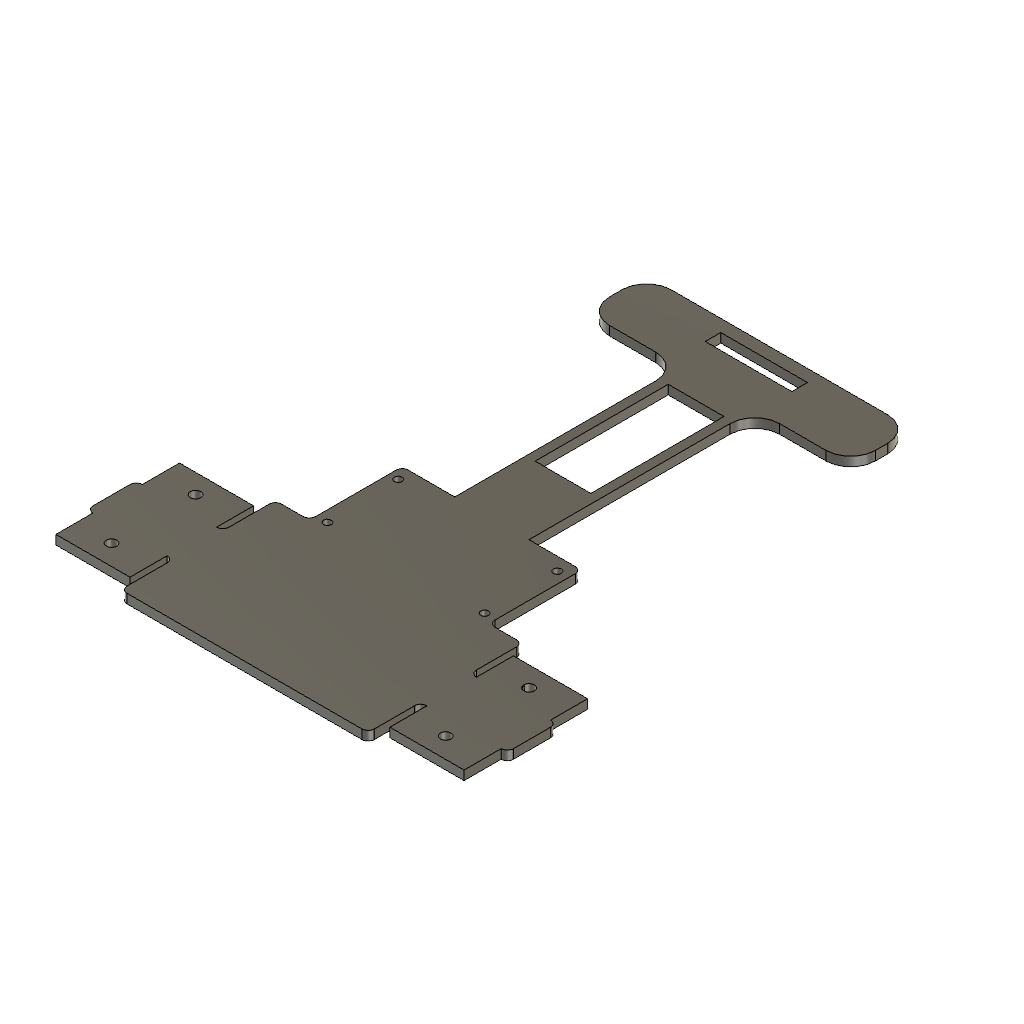
LFR Chassis (Autodesk Fusion 360 design; units mm, degrees)
part number: 2026-11-09-15-47-56-464
Autodesk Fusion 360 part; units mm, degrees
sketch "Sketch1" plane through (0, 0, 0) normal (0, 0, 1) x (1, 0, 0)
  line L0 (-30, 80) -> (10, 80)
  line L1 (10, 80) -> (10, -110)
  line L2 (10, -110) -> (-30, -110)
  line L3 (-30, -110) -> (-30, 80)
  dimension "d1" = 40
  dimension "d2" = 190
  constraint horizontal L0
  constraint vertical L1
  constraint horizontal L2
  constraint vertical L3
  measures "d1" distance of L0.start L0.end
  measures "d2" distance of L0.end L1.end
extrude "Extrude1" add sketch "Sketch1" along normal blind 3
sketch "Sketch2" plane through (10, 0, 0) normal (1, 0, 0) x (0, 1, 0)
  line L0 (-110, 0) -> (80, 0)
  line L1 (80, 0) -> (80, 3)
  line L2 (80, 3) -> (-110, 3)
  line L3 (-110, 3) -> (-110, 0)
  line L4 (80, 3) -> (50, 3)
  line L5 (50, 3) -> (50, 0)
  line L6 (50, 0) -> (80, 0)
  line L7 (80, 0) -> (80, 3)
  line L8 (80, 3) -> (50, 3)
  line L9 (50, 3) -> (50, 0)
  line L10 (50, 0) -> (80, 0)
  line L11 (80, 0) -> (80, 3)
  dimension "d5" = 30
  constraint horizontal L4
  constraint vertical L5
  constraint horizontal L6
  constraint vertical L7
  constraint coincident L1.end L2.start
  constraint horizontal L8
  constraint vertical L9
  constraint horizontal L10
  constraint vertical L11
  measures "d5" distance of L1.end L4.end
extrude "Extrude2" add sketch "Sketch2" along normal blind 45 contours L0 L1 L2 L4 L5 L6 L7 L8 L9 L10 L11
sketch "Sketch3" plane through (-30, 0, 0) normal (-1, 0, 0) x (0, -1, 0)
  line L0 (-80, 0) -> (110, 0)
  line L1 (110, 0) -> (110, 3)
  line L2 (110, 3) -> (-80, 3)
  line L3 (-80, 3) -> (-80, 0)
  line L4 (-80, 3) -> (-50, 3)
  line L5 (-50, 3) -> (-50, 0)
  line L6 (-50, 0) -> (-80, 0)
  line L7 (-80, 0) -> (-80, 3)
  constraint horizontal L4
  constraint vertical L5
  constraint horizontal L6
  constraint vertical L7
  constraint coincident L0 L5.end
  constraint coincident L2.end L3.start
extrude "Extrude3" add sketch "Sketch3" along normal blind 45 contours L0 L2 L3 L4 L5 L6 L7
sketch "Sketch4" plane through (10, 0, 0) normal (1, 0, 0) x (0, 1, 0)
  line L0 (50, 0) -> (50, 3)
  line L1 (50, 3) -> (-110, 3)
  line L2 (-110, 3) -> (-110, 0)
  line L3 (-110, 0) -> (50, 0)
  line L4 (-110, 3) -> (-50, 3)
  line L5 (-50, 3) -> (-50, 0)
  line L6 (-50, 0) -> (-110, 0)
  line L7 (-110, 0) -> (-110, 3)
  dimension "d10" = 60
  constraint horizontal L4
  constraint vertical L5
  constraint horizontal L6
  constraint vertical L7
  constraint coincident L1.end L2.start
  measures "d10" distance of L1.end L4.end
extrude "Extrude4" add sketch "Sketch4" along normal blind 40 contours L1 L2 L3 L4 L5 L6 L7
sketch "Sketch5" plane through (-30, 0, 0) normal (-1, 0, 0) x (0, -1, 0)
  line L0 (-50, 3) -> (-50, 0)
  line L1 (-50, 0) -> (110, 0)
  line L2 (110, 0) -> (110, 3)
  line L3 (110, 3) -> (-50, 3)
  line L4 (110, 3) -> (50, 3)
  line L5 (50, 3) -> (50, 0)
  line L6 (50, 0) -> (110, 0)
  line L7 (110, 0) -> (110, 3)
  dimension "d13" = 60
  constraint horizontal L4
  constraint vertical L5
  constraint horizontal L6
  constraint vertical L7
  constraint coincident L2.end L3.start
  measures "d13" distance of L2.end L4.end
extrude "Extrude5" add sketch "Sketch5" along normal blind 40 contours L1 L2 L3 L4 L5 L6 L7
extrude "Extrude6" cut 1 faces at (10, -110, 1) along direction (0, 1, 0) blind 10
extrude "Extrude7" cut 1 faces at (50, -83.3333, 2) along direction (-1, 0, 0) blind 20
extrude "Extrude8" cut 1 faces at (-70, -66.6667, 2) along direction (1, 0, 0) blind 20
sketch "Sketch6" plane through (-50, 0, 0) normal (-1, 0, 0) x (0, -1, 0)
  line L0 (100, 0) -> (100, 3)
  line L1 (100, 3) -> (50, 3)
  line L2 (50, 3) -> (50, 0)
  line L3 (50, 0) -> (100, 0)
  line L4 (60, 3) -> (90, 3)
  line L5 (90, 3) -> (90, 0)
  line L6 (90, 0) -> (60, 0)
  line L7 (60, 0) -> (60, 3)
  constraint horizontal L4
  constraint vertical L5
  constraint horizontal L6
  constraint vertical L7
  constraint coincident L3 L5.end
  constraint coincident L1 L4.start
extrude "Extrude9" add sketch "Sketch6" along normal blind 40 contours L1 L3 L4 L5 L6 L7
sketch "Sketch7" plane through (-90, 0, 0) normal (-1, 0, 0) x (0, -1, 0)
  line L0 (60, 0) -> (90, 0)
  line L1 (90, 0) -> (90, 3)
  line L2 (90, 3) -> (60, 3)
  line L3 (60, 3) -> (60, 0)
  line L4 (60, 3) -> (90, 3)
  line L5 (90, 3) -> (90, 0)
  line L6 (90, 0) -> (60, 0)
  line L7 (60, 0) -> (60, 3)
  constraint horizontal L4
  constraint vertical L5
  constraint horizontal L6
  constraint vertical L7
  constraint coincident L0.end L1.start
  constraint coincident L2.end L3.start
extrude "Extrude10" cut sketch "Sketch7" against normal blind 12
sketch "Sketch8" plane through (30, 0, 0) normal (1, 0, 0) x (0, 1, 0)
  line L0 (-100, 3) -> (-100, 0)
  line L1 (-100, 0) -> (-50, 0)
  line L2 (-50, 0) -> (-50, 3)
  line L3 (-50, 3) -> (-100, 3)
  line L4 (-90, 3) -> (-60, 3)
  line L5 (-60, 3) -> (-60, 0)
  line L6 (-60, 0) -> (-90, 0)
  line L7 (-90, 0) -> (-90, 3)
  constraint horizontal L4
  constraint vertical L5
  constraint horizontal L6
  constraint vertical L7
  constraint coincident L1 L5.end
  constraint coincident L3 L4.start
extrude "Extrude11" add sketch "Sketch8" along normal blind 28 contours L1 L3 L4 L5 L6 L7
extrude "Extrude12" cut 1 faces at (39.3333, -60, 2) along direction (0, -1, 0) blind 7
extrude "Extrude13" cut 1 faces at (39.3333, -90, 1) along direction (0, 1, 0) blind 7
extrude "Extrude14" cut 1 faces at (-68.6667, -90, 2) along direction (0, 1, 0) blind 7
extrude "Extrude15" cut 1 faces at (-68.6667, -60, 1) along direction (0, -1, 0) blind 7
extrude "Extrude16" add 1 faces at (-36.6667, -50, 2) along direction (0, 1, 0) blind 30
extrude "Extrude17" add 1 faces at (16.6667, -50, 2) along direction (0, 1, 0) blind 30
sketch "Sketch9" plane through (-50, 0, 0) normal (-1, 0, 0) x (0, -1, 0)
  line L0 (67, 3) -> (20, 3)
  line L1 (20, 3) -> (20, 0)
  line L2 (20, 0) -> (67, 0)
  line L3 (67, 0) -> (67, 3)
  line L4 (50, 3) -> (20, 3)
  line L5 (20, 3) -> (20, 0)
  line L6 (20, 0) -> (50, 0)
  line L7 (50, 0) -> (50, 3)
  constraint horizontal L4
  constraint vertical L5
  constraint horizontal L6
  constraint vertical L7
  constraint coincident L1.end L2.start
  constraint coincident L0 L4.start
extrude "Extrude18" cut sketch "Sketch9" against normal blind 11 contours L0 L1 L2 L4 L5 L6 L7
sketch "Sketch10" plane through (30, 0, 0) normal (1, 0, 0) x (0, 1, 0)
  line L0 (-67, 0) -> (-20, 0)
  line L1 (-20, 0) -> (-20, 3)
  line L2 (-20, 3) -> (-67, 3)
  line L3 (-67, 3) -> (-67, 0)
  line L4 (-50, 3) -> (-20, 3)
  line L5 (-20, 3) -> (-20, 0)
  line L6 (-20, 0) -> (-50, 0)
  line L7 (-50, 0) -> (-50, 3)
  constraint horizontal L4
  constraint vertical L5
  constraint horizontal L6
  constraint vertical L7
  constraint coincident L0.end L1.start
  constraint coincident L2 L4.start
extrude "Extrude19" cut sketch "Sketch10" against normal blind 11 contours L0 L1 L2 L4 L5 L6 L7
sketch "Sketch11" plane through (0, 0, 7.75) normal (0, 0, 1) x (-1, 0, 0)
  line L0 (-17.94, 21.7125) -> (37.94, 21.7125)
  line L1 (37.94, 21.7125) -> (37.94, 50.2875)
  line L2 (37.94, 50.2875) -> (-17.94, 50.2875)
  line L3 (-17.94, 50.2875) -> (-17.9359, 41.0312)
  line L4 (-17.9359, 41.0312) -> (-17.8426, 41.0286)
  arc A0 (-16.9897, 40.1735) -> (-17.8426, 41.0286) centre (-17.94, 40.0785) ccw
  line L5 (-16.9897, 40.1735) -> (-16.9873, 40.0802)
  line L6 (-16.9873, 40.0802) -> (-16.9818, 31.9611)
  line L7 (-16.9818, 31.9611) -> (-16.9845, 31.8679)
  arc A1 (-17.8396, 31.0149) -> (-16.9845, 31.8679) centre (-17.9345, 31.9652) ccw
  line L8 (-17.8396, 31.0149) -> (-17.9328, 31.0125)
  line L9 (-17.9328, 31.0125) -> (-17.94, 21.7125)
  arc A2 (-16.46, 32.325) -> (-16.46, 31.325) centre (-16.46, 31.825) ccw
  line L10 (-16.46, 32.325) -> (-15.56, 32.325)
  arc A3 (-15.56, 31.325) -> (-15.56, 32.325) centre (-15.56, 31.825) ccw
  line L11 (-15.56, 31.325) -> (-16.46, 31.325)
  arc A4 (-16.46, 40.675) -> (-16.46, 39.675) centre (-16.46, 40.175) ccw
  line L12 (-16.46, 40.675) -> (-15.56, 40.675)
  arc A5 (-15.56, 39.675) -> (-15.56, 40.675) centre (-15.56, 40.175) ccw
  line L13 (-15.56, 39.675) -> (-16.46, 39.675)
  circle A6 centre (-15.4, 24.2525) radius 1.25
  circle A7 centre (-15.4, 47.7475) radius 1.25
  line L14 (-13.71, 49.55) -> (-12.01, 49.55)
  line L15 (-12.01, 49.55) -> (-12.01, 47.85)
  line L16 (-12.01, 47.85) -> (-13.71, 47.85)
  line L17 (-13.71, 47.85) -> (-13.71, 49.55)
  circle A8 centre (-12.86, 23.3) radius 0.85
  arc A9 (-13.11, 34.3) -> (-13.11, 33.25) centre (-13.11, 33.775) ccw
  line L18 (-13.11, 34.3) -> (-12.91, 34.3)
  arc A10 (-12.91, 33.25) -> (-12.91, 34.3) centre (-12.91, 33.775) ccw
  line L19 (-12.91, 33.25) -> (-13.11, 33.25)
  arc A11 (-13.11, 38.75) -> (-13.11, 37.7) centre (-13.11, 38.225) ccw
  line L20 (-13.11, 38.75) -> (-12.91, 38.75)
  arc A12 (-12.91, 37.7) -> (-12.91, 38.75) centre (-12.91, 38.225) ccw
  line L21 (-12.91, 37.7) -> (-13.11, 37.7)
  circle A13 centre (-10.32, 23.3) radius 0.85
  circle A14 centre (-10.32, 48.7) radius 0.85
  circle A15 centre (-7.78, 23.3) radius 0.85
  circle A16 centre (-7.78, 48.7) radius 0.85
  circle A17 centre (-5.24, 23.3) radius 0.85
  circle A18 centre (-5.24, 48.7) radius 0.85
  circle A19 centre (-2.7, 23.3) radius 0.85
  circle A20 centre (-2.7, 48.7) radius 0.85
  circle A21 centre (-0.16, 23.3) radius 0.85
  circle A22 centre (-0.16, 48.7) radius 0.85
  circle A23 centre (2.38, 23.3) radius 0.85
  circle A24 centre (2.38, 48.7) radius 0.85
  circle A25 centre (4.92, 23.3) radius 0.85
  circle A26 centre (4.92, 48.7) radius 0.85
  circle A27 centre (7.46, 23.3) radius 0.85
  circle A28 centre (7.46, 48.7) radius 0.85
  circle A29 centre (10, 23.3) radius 0.85
  circle A30 centre (10, 48.7) radius 0.85
  circle A31 centre (12.54, 23.3) radius 0.85
  circle A32 centre (12.54, 48.7) radius 0.85
  circle A33 centre (15.08, 23.3) radius 0.85
  circle A34 centre (15.08, 48.7) radius 0.85
  circle A35 centre (17.62, 23.3) radius 0.85
  circle A36 centre (17.62, 48.7) radius 0.85
  circle A37 centre (20.16, 23.3) radius 0.85
  circle A38 centre (20.16, 48.7) radius 0.85
  circle A39 centre (22.7, 23.3) radius 0.85
  circle A40 centre (22.7, 48.7) radius 0.85
  circle A41 centre (25.24, 23.3) radius 0.85
  circle A42 centre (25.24, 48.7) radius 0.85
  circle A43 centre (27.78, 23.3) radius 0.85
  circle A44 centre (27.78, 48.7) radius 0.85
  circle A45 centre (30.32, 23.3) radius 0.85
  circle A46 centre (30.32, 48.7) radius 0.85
  line L22 (32.01, 24.15) -> (33.71, 24.15)
  line L23 (33.71, 24.15) -> (33.71, 22.45)
  line L24 (33.71, 22.45) -> (32.01, 22.45)
  line L25 (32.01, 22.45) -> (32.01, 24.15)
  circle A47 centre (32.86, 48.7) radius 0.85
  circle A48 centre (35.4, 47.7475) radius 1.25
  circle A49 centre (36.035, 24.2525) radius 1.25
  circle A50 centre (-15.4, 24.2525) radius 1.25
  circle A51 centre (36.035, 24.2525) radius 1.25
  circle A52 centre (35.4, 47.7475) radius 1.25
  circle A53 centre (-15.4, 47.7475) radius 1.25
  constraint concentric A6 A50
  constraint concentric A49 A51
  constraint concentric A48 A52
  constraint concentric A7 A53
extrude "Extrude20" cut sketch "Sketch11" against normal blind 8 contours A6 A50 | A7 A53 | A48 A52 | A49 A51
extrude "Extrude21" cut 1 faces at (10, 26.6667, 1) along direction (-1, 0, 0) blind 8
extrude "Extrude22" cut 1 faces at (-30, 3.3333, 1) along direction (1, 0, 0) blind 8
sketch "Sketch12" plane through (0, 0, 3) normal (0, 0, 1) x (-1, 0, 0)
  line L0 (22, 20) -> (39, 20)
  line L1 (39, 20) -> (39, 50)
  line L2 (39, 50) -> (50, 50)
  line L3 (50, 50) -> (50, 67)
  line L4 (50, 67) -> (78, 67)
  line L5 (78, 67) -> (78, 83)
  line L6 (78, 83) -> (50, 83)
  line L7 (50, 83) -> (50, 100)
  line L8 (50, 100) -> (-30, 100)
  line L9 (-30, 100) -> (-30, 83)
  line L10 (-30, 83) -> (-58, 83)
  line L11 (-58, 83) -> (-58, 67)
  line L12 (-58, 67) -> (-30, 67)
  line L13 (-30, 67) -> (-30, 50)
  line L14 (-30, 50) -> (-19, 50)
  line L15 (-19, 50) -> (-19, 20)
  line L16 (-19, 20) -> (-2, 20)
  line L17 (-2, 20) -> (-2, -50)
  line L18 (-2, -50) -> (-55, -50)
  line L19 (-55, -50) -> (-55, -80)
  line L20 (-55, -80) -> (75, -80)
  line L21 (75, -80) -> (75, -50)
  line L22 (75, -50) -> (22, -50)
  line L23 (22, -50) -> (22, 20)
  circle A0 centre (-15.4, 47.7475) radius 1.25
  circle A1 centre (-15.4, 24.2525) radius 1.25
  circle A2 centre (35.4, 47.7475) radius 1.25
  circle A3 centre (36.035, 24.2525) radius 1.25
  line L24 (45, -75) -> (-25, -75)
  line L25 (-25, -75) -> (-25, -60)
  line L26 (-25, -60) -> (45, -60)
  line L27 (45, -60) -> (45, -75)
  constraint horizontal L24
  constraint vertical L25
  constraint horizontal L26
  constraint vertical L27
extrude "Extrude23" cut sketch "Sketch12" against normal blind 3 contours L24 L25 L26 L27
extrude "Extrude24" add 1 faces at (-21.6667, 75, 2) along direction (0, -1, 0) blind 6
extrude "Extrude25" add 1 faces at (1.6667, 60, 2) along direction (0, 1, 0) blind 4
extrude "Extrude26" add 1 faces at (-45, 65.6667, 2) along direction (1, 0, 0) blind 28
extrude "Extrude27" cut 1 faces at (-17, 65.6667, 2) along direction (-1, 0, 0) blind 8
extrude "Extrude28" add 1 faces at (25, 67.3333, 2) along direction (-1, 0, 0) blind 22
extrude "Extrude29" cut 2 faces at (19.6667, 50, 2) (-57.3333, 50, 1) along direction (0, 1, 0) blind 3
extrude "Extrude30" cut 1 faces at (11.6667, 80, 2) along direction (0, -1, 0) blind 7
extrude "Extrude31" cut 1 faces at (-75, 66.3333, 2) along direction (1, 0, 0) blind 28
extrude "Extrude32" cut 1 faces at (55, 59.6667, 2) along direction (-1, 0, 0) blind 22
extrude "Extrude33" add 1 faces at (-47, 66.3333, 2) along direction (-1, 0, 0) blind 6
fillet "Fillet1" radius 8 6 edges at (-53, 73, 1.5) (-53, 53, 1.5) (-22, 53, 1.5) (2, 53, 1.5) (33, 53, 1.5) (33, 73, 1.5)
sketch "Sketch13" plane through (0, 0, 3) normal (0, 0, 1) x (-1, 0, 0)
  circle A0 centre (36.035, 24.2525) radius 1.25
  circle A1 centre (35.4, 47.7475) radius 1.25
  circle A2 centre (-15.4, 24.2525) radius 1.25
  circle A3 centre (-15.4, 47.7475) radius 1.25
  line L0 (-3, -64) -> (25, -64)
  line L1 (25, -64) -> (25, -69)
  line L2 (25, -69) -> (-3, -69)
  line L3 (-3, -69) -> (-3, -64)
  arc A4 (-33, -65) -> (-25, -73) centre (-25, -65) ccw
  line L4 (-25, -73) -> (45, -73)
  arc A5 (45, -73) -> (53, -65) centre (45, -65) ccw
  line L5 (53, -65) -> (53, -61)
  arc A6 (53, -61) -> (45, -53) centre (45, -61) ccw
  line L6 (45, -53) -> (30, -53)
  arc A7 (22, -45) -> (30, -53) centre (30, -45) ccw
  line L7 (22, -45) -> (22, 20)
  line L8 (22, 20) -> (39, 20)
  line L9 (39, 20) -> (39, 50)
  line L10 (39, 50) -> (50, 50)
  line L11 (50, 50) -> (50, 67)
  line L12 (50, 67) -> (78, 67)
  line L13 (78, 67) -> (78, 83)
  line L14 (78, 83) -> (50, 83)
  line L15 (50, 83) -> (50, 100)
  line L16 (50, 100) -> (-30, 100)
  line L17 (-30, 100) -> (-30, 83)
  line L18 (-30, 83) -> (-58, 83)
  line L19 (-58, 83) -> (-58, 67)
  line L20 (-58, 67) -> (-30, 67)
  line L21 (-30, 67) -> (-30, 50)
  line L22 (-30, 50) -> (-19, 50)
  line L23 (-19, 50) -> (-19, 20)
  line L24 (-19, 20) -> (-2, 20)
  line L25 (-2, 20) -> (-2, -45)
  arc A8 (-10, -53) -> (-2, -45) centre (-10, -45) ccw
  line L26 (-10, -53) -> (-25, -53)
  arc A9 (-25, -53) -> (-33, -61) centre (-25, -61) ccw
  line L27 (-33, -61) -> (-33, -65)
  line L28 (19, -3) -> (1, -3)
  line L29 (1, -3) -> (1, -46)
  line L30 (1, -46) -> (19, -46)
  line L31 (19, -46) -> (19, -3)
  constraint horizontal L28
  constraint vertical L29
  constraint horizontal L30
  constraint vertical L31
extrude "Extrude34" cut sketch "Sketch13" against normal blind 3 contours L28 L29 L30 L31
fillet "Fillet2" radius 2 16 edges at (19, -20, 1.5) (-39, -20, 1.5) (-50, -50, 1.5) (-39, -50, 1.5) (30, -50, 1.5) (19, -50, 1.5) (30, -67, 1.5) (58, -67, 1.5) (58, -83, 1.5) (30, -100, 1.5) (30, -83, 1.5) (-50, -100, 1.5) (-50, -83, 1.5) (-78, -83, 1.5) (-78, -67, 1.5) (-50, -67, 1.5)
extrude "Extrude35" add 1 faces at (40, -83, 1) along direction (0, -1, 0) blind 17
extrude "Extrude36" add 1 faces at (40, -67, 2) along direction (0, 1, 0) blind 17
extrude "Extrude37" add 1 faces at (-60, -67, 1) along direction (0, 1, 0) blind 12
extrude "Extrude38" add 1 faces at (-60, -83, 2) along direction (0, -1, 0) blind 12
extrude "Extrude39" cut 1 faces at (40, -100, 1) along direction (0, 1, 0) blind 17
extrude "Extrude40" add 1 faces at (40, -83, 1) along direction (0, -1, 0) blind 12
extrude "Extrude41" cut 1 faces at (40, -50, 2) along direction (0, -1, 0) blind 17
extrude "Extrude42" add 1 faces at (40, -67, 2) along direction (0, 1, 0) blind 12
sketch "Sketch14" plane through (0, 0, 5.1938) normal (0, 0, 1) x (-1, 0, 0)
  line L0 (-50.5, 83.3062) -> (-36.5, 83.3062)
  line L1 (-36.5, 83.3062) -> (-36.5, 93.3062)
  line L2 (-36.5, 93.3062) -> (-50.5, 93.3062)
  line L3 (-50.5, 93.3062) -> (-50.5, 83.3062)
  circle A0 centre (-43.5, 88.5167) radius 1.7
  circle A1 centre (-43.5, 61.4707) radius 1.7
  circle A2 centre (-43.5, 88.4365) radius 1.7
  dimension "d94" = 3.4
  dimension "d95" = 3.4
  measures "d94" diameter of A0
  measures "d95" diameter of A1
extrude "Extrude43" cut sketch "Sketch14" against normal blind 2.5 contours A1
sketch "Sketch15" plane through (0, 0, 3) normal (0, 0, 1) x (-1, 0, 0)
  circle A0 centre (-43.5, 61.4707) radius 1.7
  arc A1 (-30, 65) -> (-32, 67) centre (-32, 65) ccw
  line L0 (-30, 65) -> (-30, 52)
  arc A2 (-30, 52) -> (-28, 50) centre (-28, 52) ccw
  line L1 (-28, 50) -> (-21, 50)
  arc A3 (-19, 48) -> (-21, 50) centre (-21, 48) ccw
  line L2 (-19, 48) -> (-19, 22)
  arc A4 (-19, 22) -> (-17, 20) centre (-17, 22) ccw
  line L3 (-17, 20) -> (-2, 20)
  line L4 (-2, 20) -> (-2, -45)
  arc A5 (-10, -53) -> (-2, -45) centre (-10, -45) ccw
  line L5 (-10, -53) -> (-25, -53)
  arc A6 (-25, -53) -> (-33, -61) centre (-25, -61) ccw
  line L6 (-33, -61) -> (-33, -65)
  arc A7 (-33, -65) -> (-25, -73) centre (-25, -65) ccw
  line L7 (-25, -73) -> (45, -73)
  arc A8 (45, -73) -> (53, -65) centre (45, -65) ccw
  line L8 (53, -65) -> (53, -61)
  arc A9 (53, -61) -> (45, -53) centre (45, -61) ccw
  line L9 (45, -53) -> (30, -53)
  arc A10 (22, -45) -> (30, -53) centre (30, -45) ccw
  line L10 (22, -45) -> (22, 20)
  line L11 (22, 20) -> (37, 20)
  arc A11 (37, 20) -> (39, 22) centre (37, 22) ccw
  line L12 (39, 22) -> (39, 48)
  arc A12 (41, 50) -> (39, 48) centre (41, 48) ccw
  line L13 (41, 50) -> (48, 50)
  arc A13 (48, 50) -> (50, 52) centre (48, 52) ccw
  line L14 (50, 52) -> (50, 65)
  arc A14 (52, 67) -> (50, 65) centre (52, 65) ccw
  line L15 (52, 67) -> (52, 55)
  line L16 (52, 55) -> (76, 55)
  line L17 (76, 55) -> (76, 67)
  arc A15 (76, 67) -> (78, 69) centre (76, 69) ccw
  line L18 (78, 69) -> (78, 81)
  arc A16 (78, 81) -> (76, 83) centre (76, 81) ccw
  line L19 (76, 83) -> (76, 95)
  line L20 (76, 95) -> (52, 95)
  line L21 (52, 95) -> (52, 83)
  arc A17 (50, 85) -> (52, 83) centre (52, 85) ccw
  line L22 (50, 85) -> (50, 98)
  arc A18 (50, 98) -> (48, 100) centre (48, 98) ccw
  line L23 (48, 100) -> (-28, 100)
  arc A19 (-28, 100) -> (-30, 98) centre (-28, 98) ccw
  line L24 (-30, 98) -> (-30, 85)
  arc A20 (-32, 83) -> (-30, 85) centre (-32, 85) ccw
  line L25 (-32, 83) -> (-32, 95)
  line L26 (-32, 95) -> (-56, 95)
  line L27 (-56, 95) -> (-56, 83)
  arc A21 (-56, 83) -> (-58, 81) centre (-56, 81) ccw
  line L28 (-58, 81) -> (-58, 69)
  arc A22 (-58, 69) -> (-56, 67) centre (-56, 69) ccw
  line L29 (-56, 67) -> (-56, 55)
  line L30 (-56, 55) -> (-32, 55)
  line L31 (-32, 55) -> (-32, 67)
  line L32 (1, -3) -> (19, -3)
  line L33 (19, -3) -> (19, -46)
  line L34 (19, -46) -> (1, -46)
  line L35 (1, -46) -> (1, -3)
  circle A23 centre (36.035, 24.2525) radius 1.25
  circle A24 centre (35.4, 47.7475) radius 1.25
  circle A25 centre (-15.4, 24.2525) radius 1.25
  circle A26 centre (-15.4, 47.7475) radius 1.25
  line L36 (-3, -64) -> (25, -64)
  line L37 (25, -64) -> (25, -69)
  line L38 (25, -69) -> (-3, -69)
  line L39 (-3, -69) -> (-3, -64)
  circle A27 centre (-43.5017, 61.301) radius 1.701
  circle A28 centre (-43.4917, 88.4249) radius 1.6934
  circle A29 centre (64.5053, 61.3102) radius 1.7102
  circle A30 centre (64.515, 88.4524) radius 1.6967
extrude "Extrude44" cut sketch "Sketch15" against normal blind 3 contours A0 A27 | A28 | A29 | A30 picked at (-43.4653, 60.8489)
